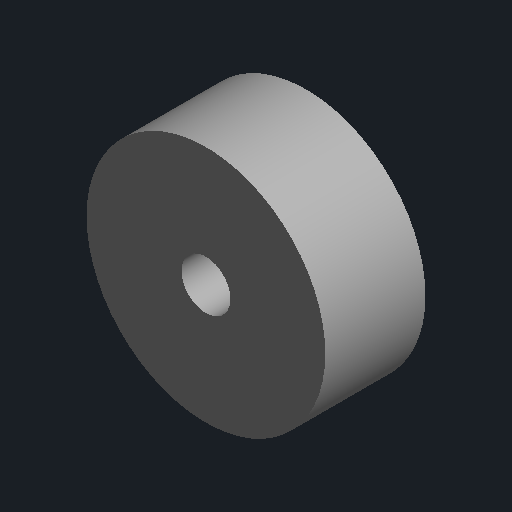
# Autodesk Inventor part: Rueda_VWheel_POM
Saved by Autodesk Inventor 2027.2 (Build 312334000, 334)
## iProperties
Part Number: Rueda_VWheel_POM
Material: Genérico
Document SubType Name: Modelado
Designer: Usuario
Appearance: Por defecto
Author: Usuario
Autodesk Inventor part; units mm, degrees
ref_plane "Plano YZ" through (0, 0, 0) normal (1, 0, 0) x (0, 1, 0)
ref_plane "Plano XZ" through (0, 0, 0) normal (0, 1, 0) x (-1, 0, 0)
ref_plane "Plano XY" through (0, 0, 0) normal (0, 0, 1) x (1, 0, 0)
sketch "Boceto1" plane through (0, 0, 0) normal (0, 0, 1) x (1, 0, 0)
  circle A0 centre (0, 0) radius 12.195
  circle A1 centre (0, 0) radius 2.5
  dimension "d0" = 10.23
  constraints: 2 centre point
extrude "Extrusión1" add sketch "Boceto1" along normal mid plane 10.23
